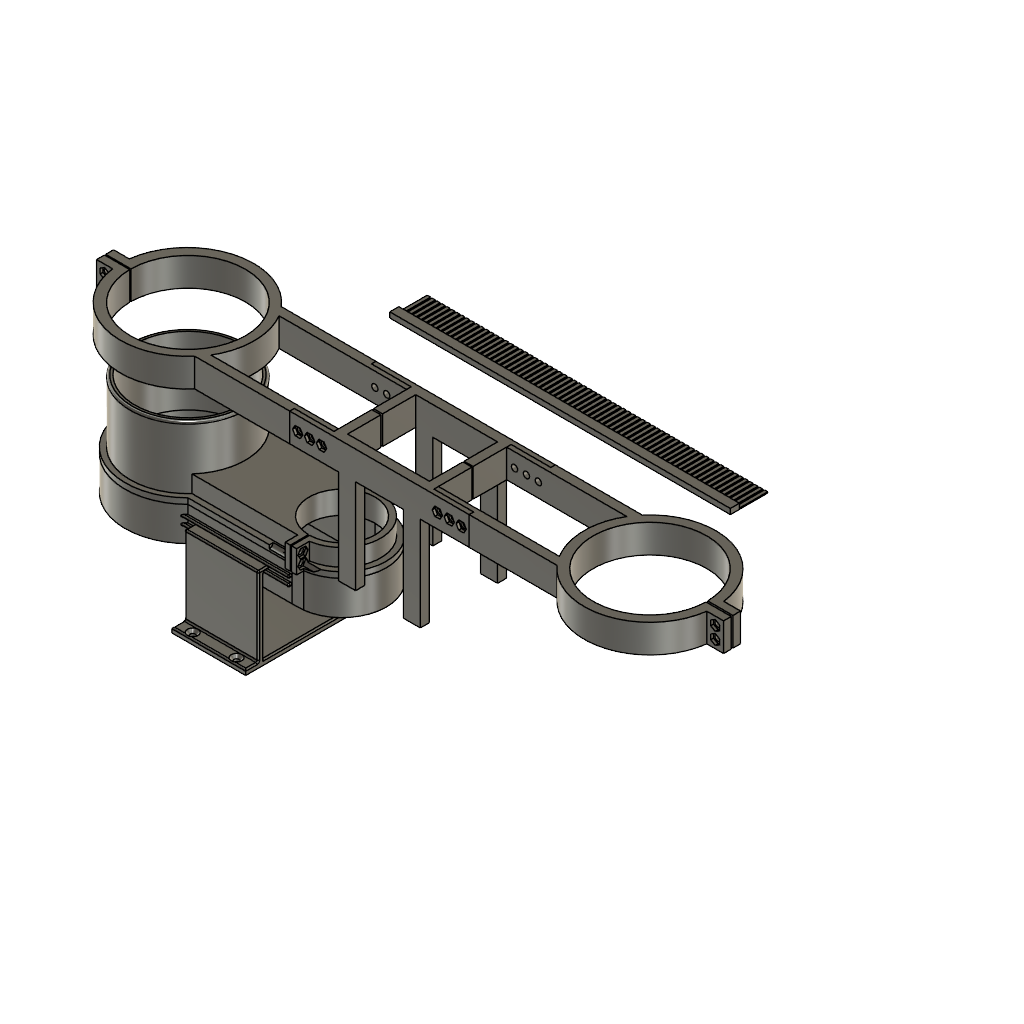
cnc-dust-shoe (Autodesk Fusion 360 design; units mm, degrees)
part number: 2026-10-06-19-06-41-625
Autodesk Fusion 360 part; units mm, degrees
(part 1 of 2)
sketch "Sketch1" plane through (0, 0, 0) normal (0, 0, 1) x (1, 0, 0)
  line L0 (-0.0662, 34.0001) -> (-170.0662, 34.0001)
  line L1 (-170.0662, 34.0001) -> (-170.0662, -34.0001)
  line L2 (-170.0662, -34.0001) -> (-5.0662, -34.0001)
  line L3 (4.9338, -33.6402) -> (4.9338, -44.9999)
  line L4 (-5.0662, -44.9999) -> (-5.0662, -34.0001)
  line L5 (-0.5662, -28.9945) -> (-0.5662, -44.9999)
  line L6 (0.4287, -28.9968) -> (0.4287, -44.9999)
  line L7 (4.9338, -44.9999) -> (0.4287, -44.9999)
  line L8 (-0.5662, -44.9999) -> (-5.0662, -44.9999)
  arc A0 (4.9338, -33.6402) -> (-0.0662, 34.0001) centre (0, 0) ccw
  arc A1 (0.4287, -28.9968) -> (-0.5662, -28.9945) centre (0, 0) ccw
  arc A2 (4.9338, -33.6402) -> (-5.0662, -33.6206) centre (0, 0) ccw
  line L9 (-5.0662, -34.0001) -> (-5.0662, -33.6206)
  dimension "d1" = 58
  dimension "d3" = 170
  constraint coincident A0.centre A1.centre
  constraint horizontal L0
  constraint vertical L1
  constraint horizontal L2
  constraint vertical L3
  constraint horizontal L7
  constraint vertical L4
  constraint collinear L7 L8
  constraint concentric A0 A1
  constraint vertical L5
  constraint vertical L6
  constraint concentric A0 A2
  constraint perpendicular L2 L9
  measures "d1" diameter of A1
  measures "d3" distance of L0.start L0.end
extrude "Extrude1" add sketch "Sketch1" along normal blind 20 makes body 1
sketch "Sketch2" plane through (0, 0, 20) normal (0, 0, 1) x (-1, 0, 0)
  arc A0 (-4.9338, 33.6402) -> (0.0662, -34.0001) centre (0, 0) ccw
  line L0 (0.0662, -34.0001) -> (170.0662, -34.0001)
  line L1 (170.0662, -34.0001) -> (170.0662, 34.0001)
  line L2 (170.0662, 34.0001) -> (5.0662, 34.0001)
  circle A1 centre (135.7962, 0.0001) radius 50.7
  circle A2 centre (135.7962, 0.0001) radius 46.7
  line L3 (5.0662, 34.0001) -> (5.0662, 44.9999)
  line L4 (5.0662, 44.9999) -> (0.5662, 44.9999)
  line L5 (0.5662, 44.9999) -> (0.5662, 28.9945)
  arc A3 (-0.4287, 28.9968) -> (0.5662, 28.9945) centre (0, 0) ccw
  line L6 (-0.4287, 28.9968) -> (-0.4287, 44.9999)
  line L7 (-0.4287, 44.9999) -> (-4.9338, 44.9999)
  line L8 (-4.9338, 44.9999) -> (-4.9338, 33.6402)
  circle A4 centre (135.7962, 0.0001) radius 55.2
  line L9 (98.1865, 34.0001) -> (5.0662, 34.0001)
  line L10 (5.0662, 34.0001) -> (5.0662, 39.0001)
  line L11 (5.0662, 39.0001) -> (98.1865, 39.0001)
  line L12 (98.1865, 39.0001) -> (98.1865, 34.0001)
  line L13 (0.0662, -34.0001) -> (96.7318, -34.0001)
  line L14 (96.7318, -34.0001) -> (96.7318, -39.0001)
  line L15 (96.7318, -39.0001) -> (0.0662, -39.0001)
  line L16 (0.0662, -39.0001) -> (0.0662, -34.0001)
  arc A5 (-4.9338, 38.6868) -> (0.0662, -39.0001) centre (0, 0) ccw
  point P0 (135.7962, 0.0001)
  dimension "d9" = 101.4
  dimension "d12" = -4
  dimension "d189" = 110.4
  dimension "d190" = 5
  dimension "d191" = 5
  dimension "d192" = 5
  constraint coincident P0 A1.centre
  constraint horizontal L9
  constraint vertical L10
  constraint horizontal L11
  constraint vertical L12
  constraint coincident A1 L9.start
  constraint coincident L2 L9.start
  constraint horizontal L13
  constraint vertical L14
  constraint horizontal L15
  constraint vertical L16
  constraint coincident A4 L14.end
  constraint coincident A0.end L0.start
  constraint coincident L8 A5.start
  measures "d9" diameter of A1
  measures "d189" diameter of A4
  measures "d190" distance of L9.start L11.end
  measures "d191" distance of A0.end L15.end
extrude "Extrude3" add sketch "Sketch2" along normal blind 40 and the other way blind 20 contours L0 L2 A1 A2 | L0 L1 L2 A1 A2 | L0 L1 L2 A2 | L0 A2 | L2 A2 | L0 L1 A2 | L1 L2 A2 | L1 A2 bodies 1
extrude "Extrude19" add sketch "Sketch2" along normal blind 5 from surface at -20 contours A0 L8 L16 A5 | L0 A4 L13 L15 L16 | L0 A4 L13 L14 | L0 A1 A4 L11 L12 L14 | L2 A4 L9 L11 L12 | L2 L3 A4 L9 L10 L11 bodies 1
sketch "Sketch5" plane through (0, 0, 60) normal (0, 0, 1) x (-1, 0, 0)
  circle A0 centre (135.7962, 0.0001) radius 46.7
extrude "Extrude5" cut sketch "Sketch5" against normal through all bodies 1
sketch "Sketch6" plane through (0, 0, 0) normal (0, 0, -1) x (1, 0, 0)
  line L0 (-170.0662, -34.0001) -> (-170.0662, 34.0001)
  line L1 (-0.0662, -34.0001) -> (-170.0662, -34.0001)
  line L2 (-170.0662, 34.0001) -> (-5.0662, 34.0001)
  circle A0 centre (-135.7962, 0.0001) radius 46.7
  line L3 (-0.5662, 28.9945) -> (-99.1962, 28.9945)
  line L4 (-99.1962, 28.9945) -> (-99.1962, -29.0055)
  line L5 (-99.1962, -29.0055) -> (-0.5662, -29.0055)
  line L6 (-0.5662, -29.0055) -> (-0.5662, 28.9945)
  arc A1 (-5.0662, 33.6206) -> (4.9338, 33.6402) centre (0, 0) ccw
  point P0 (-0.5662, 28.9945)
  dimension "d27" = 58
  constraint horizontal L3
  constraint vertical L4
  constraint horizontal L5
  constraint vertical L6
  constraint coincident A0 L4.end
  constraint coincident P0 L3.start
  measures "d27" distance of L3.end L4.end
extrude "Extrude6" cut sketch "Sketch6" against normal blind 18 contours L0 A0 | L0 L1 L2 A0 L3 L4 | L1 A0 | L2 A0 | A0 L3 L4 | A0 L3 L5 A1 bodies 1
sketch "Sketch7" plane through (4.9338, 0, 0) normal (1, 0, 0) x (0, 1, 0)
  line L0 (-44.9999, 0) -> (-38.6868, 0)
  line L1 (-33.6402, 5) -> (-33.6402, 20)
  line L2 (-33.6402, 20) -> (-44.9999, 20)
  line L3 (-44.9999, 20) -> (-44.9999, 0)
  line L4 (-33.6402, 0) -> (-44.9999, 0)
  line L5 (-41.5573, 18.1607) -> (-43.7945, 14.2857)
  line L6 (-43.7945, 14.2857) -> (-41.5573, 10.4107)
  line L7 (-41.5573, 10.4107) -> (-37.0829, 10.4107)
  line L8 (-37.0829, 10.4107) -> (-34.8456, 14.2857)
  line L9 (-34.8456, 14.2857) -> (-37.0829, 18.1607)
  line L10 (-37.0829, 18.1607) -> (-41.5573, 18.1607)
  line L11 (-41.5573, 9.5893) -> (-43.7945, 5.7143)
  line L12 (-43.7945, 5.7143) -> (-41.5573, 1.8393)
  line L13 (-41.5573, 1.8393) -> (-37.0829, 1.8393)
  line L14 (-37.0829, 1.8393) -> (-34.8456, 5.7143)
  line L15 (-34.8456, 5.7143) -> (-37.0829, 9.5893)
  line L16 (-37.0829, 9.5893) -> (-41.5573, 9.5893)
  circle A0 centre (-39.3201, 14.2857) radius 2.5
  circle A1 centre (-39.3201, 5.7143) radius 2.5
  circle A2 centre (-39.3201, 5.7143) radius 3.875
  line L17 (-38.6868, 0) -> (-38.6868, 5)
  line L18 (-38.6868, 5) -> (-33.6402, 5)
  point P0 (-39.3201, 14.2857)
  point P1 (-39.3201, 5.7143)
  point P2 (-39.3201, 14.2857)
  point P3 (-39.3201, 5.7143)
  dimension "d40" = 20
  dimension "d41" = 5.7143
  dimension "d43" = 3.875
  dimension "d44" = 3.875
  dimension "d45" = 5
  dimension "d46" = 5
  constraint coincident P2 P0
  constraint coincident P3 P1
  constraint concentric A1 A2
  constraint tangent L12 A2
  measures "d40" distance of L0.start L2.end
  measures "d41" distance of P3 L4
  measures "d43" distance of P2 L10
  measures "d44" distance of P3 L16
  measures "d45" diameter of A0
  measures "d46" diameter of A1
extrude "Extrude9" cut sketch "Sketch7" along normal mid plane 40 contours A1 L17 L18 | A1 L17 L18 | A0 bodies 1
extrude "Extrude10" cut sketch "Sketch7" along normal blind -2.25 and the other way blind -15 contours L13 L14 A2 L17 | L13 A2 L17 | L12 L13 A2 | A1 A2 L17 L18 | A1 A2 L17 L18 | L11 L12 A2 | L14 A2 L18 | L14 L15 A2 L18 | L11 L16 A2 | L15 L16 A2 | L5 L6 L7 L8 L9 L10 bodies 1
fillet "Fillet3" radius 2 curvature continuous 1 edges at (-88.5272, 18.3338, 60) on bodies 1
ref_plane "WorkPlane1" through (-30.9732, -5.4691, 90) normal (0, 0, 1) x (-1, 0, 0)
sketch "Sketch9" plane through (0, 0, 90) normal (0, 0, 1) x (1, 0, 0)
  circle A0 centre (-135.7962, -0.0001) radius 50.7
  line L0 (34.9038, 29.9999) -> (106.9038, 29.9999)
  line L1 (106.9038, -30.0001) -> (34.9038, -30.0001)
  line L2 (114.9038, -38.0001) -> (26.9038, -38.0001)
  line L3 (26.9038, 37.9999) -> (114.9038, 37.9999)
  line L4 (26.9038, -38.0001) -> (-91.8897, -38.0001)
  line L5 (26.9038, 37.9999) -> (-91.5487, 37.9999)
  line L6 (26.9038, 29.9718) -> (-85.4827, 29.9718)
  line L7 (26.9038, -29.972) -> (-85.4836, -29.972)
  arc A1 (-85.4836, -29.972) -> (-85.4827, 29.9718) centre (-136.4963, 0.0007) ccw
  line L8 (-208.7962, 7.4999) -> (-193.7962, 7.4999)
  line L9 (-193.7962, -7.5001) -> (-208.7962, -7.5001)
  arc A2 (-91.5487, 37.9999) -> (-194.8742, 7.4999) centre (-136.4963, 0.0007) ccw
  arc A3 (-194.6129, -7.5001) -> (-91.8897, -38.0001) centre (-136.4963, 0.0007) ccw
  line L10 (114.9038, 29.9999) -> (114.9038, 7.4999)
  line L11 (114.9038, -7.5001) -> (114.9038, -30.0001)
  line L12 (106.9038, -0.5001) -> (114.9038, -0.5001)
  line L13 (106.9038, 0.4999) -> (114.9038, 0.4999)
  line L14 (106.9038, 29.9999) -> (106.9038, 0.4999)
  line L15 (106.9038, -0.5001) -> (106.9038, -30.0001)
  line L16 (-186.4938, 0.4968) -> (-208.7962, 0.4966)
  line L17 (-186.4938, -0.5002) -> (-208.7962, -0.5002)
  line L18 (-208.7962, -7.5001) -> (-208.7962, -0.5002)
  line L19 (-208.7962, 0.4966) -> (-208.7962, 7.4999)
  arc A4 (-186.4938, -0.5002) -> (-186.4938, 0.4968) centre (-136.4963, 0.0007) ccw
  line L20 (114.9038, 37.9999) -> (226.4769, 37.9999)
  line L21 (227.3442, -38.0001) -> (114.9038, -38.0001)
  line L22 (114.9038, 29.9999) -> (220.7859, 29.9999)
  line L23 (221.3903, -30.0001) -> (114.9038, -30.0001)
  line L24 (114.9038, -30.0001) -> (114.9038, -0.5001)
  line L25 (114.9038, 0.4999) -> (114.9038, 29.9999)
  line L26 (106.9038, 0.4999) -> (345.5642, 0.4999) construction
  arc A5 (220.7859, 29.9999) -> (221.3903, -30.0001) centre (270.7233, 0.4999) ccw
  line L27 (328.2364, 7.9999) -> (343.0085, 7.9999)
  line L28 (343.0085, -7.0001) -> (328.2364, -7.0001)
  arc A6 (227.3442, -38.0001) -> (328.2364, -7.0001) centre (270.7233, 0.4999) ccw
  arc A7 (328.2364, 7.9999) -> (226.4769, 37.9999) centre (270.7233, 0.4999) ccw
  line L29 (343.0085, 1.2499) -> (320.7177, 1.2499)
  line L30 (343.0085, -0.25) -> (320.7177, -0.25)
  arc A8 (320.7177, 1.2499) -> (320.7177, -0.25) centre (270.7233, 0.4999) ccw
  line L31 (343.0085, 7.9999) -> (343.0085, 1.2499)
  line L32 (343.0085, -0.25) -> (343.0085, -7.0001)
  line L33 (34.9038, 0.7499) -> (26.9038, 0.7499)
  line L34 (34.9038, -0.7501) -> (26.9038, -0.7501)
  line L35 (26.9038, -29.972) -> (26.9038, -0.7501)
  line L36 (26.9038, 0.7499) -> (26.9038, 29.9718)
  line L37 (34.9038, -30.0001) -> (34.9038, -0.7501)
  line L38 (34.9038, 0.7499) -> (34.9038, 29.9999)
  line L39 (34.9038, 29.9999) -> (49.9038, 29.9999)
  line L40 (49.9038, 29.9999) -> (49.9038, 37.9999)
  line L41 (49.9038, 37.9999) -> (34.9038, 37.9999)
  line L42 (34.9038, 37.9999) -> (34.9038, 29.9999)
  line L43 (106.9038, 29.9999) -> (91.9038, 29.9999)
  line L44 (91.9038, 29.9999) -> (91.9038, 37.9999)
  line L45 (91.9038, 37.9999) -> (106.9038, 37.9999)
  line L46 (106.9038, 37.9999) -> (106.9038, 29.9999)
  line L47 (106.9038, -30.0001) -> (91.9038, -30.0001)
  line L48 (91.9038, -30.0001) -> (91.9038, -38.0001)
  line L49 (91.9038, -38.0001) -> (106.9038, -38.0001)
  line L50 (106.9038, -38.0001) -> (106.9038, -30.0001)
  line L51 (34.9038, -30.0001) -> (49.9038, -30.0001)
  line L52 (49.9038, -30.0001) -> (49.9038, -38.0001)
  line L53 (49.9038, -38.0001) -> (34.9038, -38.0001)
  line L54 (34.9038, -38.0001) -> (34.9038, -30.0001)
  line L55 (26.9038, 33.9999) -> (-8.0962, 33.9999)
  line L56 (-8.0962, 33.9999) -> (26.9038, 33.9999)
  line L57 (26.9038, 33.9999) -> (26.9038, 29.9718)
  line L58 (-8.0962, 33.9999) -> (-8.0962, 37.9999)
  line L59 (114.9038, -34.0001) -> (149.9038, -34.0001)
  line L60 (149.9038, -34.0001) -> (149.9038, -38.0001)
  line L61 (114.9038, -34.0001) -> (114.9038, -30.0001)
  line L62 (114.9038, 29.9999) -> (114.9038, 33.9999)
  line L63 (114.9038, 33.9999) -> (149.9038, 33.9999)
  line L64 (149.9038, 33.9999) -> (149.9038, 37.9999)
  line L65 (26.9038, -34.0001) -> (-8.0962, -34.0001)
  line L66 (-8.0962, -34.0001) -> (-8.0962, -38.0001)
  line L67 (26.9038, -34.0001) -> (26.9038, -29.972)
  point P0 (-135.7962, -0.0001)
  point P1 (-85.0962, -0.0001)
  point P2 (-185.9147, -0.0001)
  point P3 (106.9038, -0.0001)
  point P4 (129.9038, -0.0001)
  dimension "d65" = 72
  dimension "d66" = 60
  dimension "d67" = 120
  dimension "d69" = 8
  dimension "d70" = 8
  dimension "d71" = 8
  dimension "d72" = 8
  dimension "d73" = 100
  dimension "d79" = 15
  dimension "d80" = 15
  dimension "d81" = 15
  dimension "d92" = 76
  dimension "d95" = 100
  dimension "d97" = 8
  dimension "d99" = 8
  dimension "d128" = 15
  dimension "d129" = 8
  dimension "d130" = 15
  dimension "d131" = 8
  dimension "d132" = 15
  dimension "d133" = 8
  dimension "d134" = 15
  dimension "d135" = 8
  dimension "d138" = 35
  dimension "d139" = 4
  dimension "d140" = 35
  dimension "d141" = 4
  dimension "d142" = 35
  dimension "d143" = 4
  dimension "d152" = 35
  dimension "d153" = 4
  constraint horizontal L0
  constraint vertical L14
  constraint horizontal L1
  constraint vertical L37
  constraint coincident A0 P1
  constraint perpendicular L4 L35
  constraint perpendicular L5 L36
  constraint perpendicular L6 L38
  constraint perpendicular L7 L37
  constraint concentric A1 A4
  constraint concentric A1 A2
  constraint horizontal L8
  constraint horizontal L9
  constraint vertical L18
  constraint coincident L8 A2.end
  constraint concentric A2 A3
  constraint coincident L9 A3.start
  constraint collinear L10 L11
  constraint collinear L14 L15
  constraint coincident P3 L14
  constraint collinear L18 L19
  constraint coincident L17 A4.start
  constraint coincident A0 L16.start
  constraint horizontal L20
  constraint horizontal L21
  constraint vertical L24
  constraint collinear L24 L25
  constraint perpendicular L24 L26
  constraint coincident L26 A5.centre
  constraint concentric A6 A8
  constraint concentric A5 A7
  constraint horizontal L27
  constraint vertical L31
  constraint horizontal L28
  constraint concentric A6 A7
  constraint collinear L31 L32
  constraint collinear L35 L36
  constraint collinear L37 L38
  constraint horizontal L39
  constraint vertical L40
  constraint horizontal L41
  constraint vertical L42
  constraint horizontal L43
  constraint vertical L44
  constraint horizontal L45
  constraint vertical L46
  constraint horizontal L47
  constraint vertical L48
  constraint horizontal L49
  constraint vertical L50
  constraint horizontal L51
  constraint vertical L52
  constraint horizontal L53
  constraint vertical L54
  constraint perpendicular L36 L55
  constraint perpendicular L6 L57
  constraint coincident L5 L58.end
  constraint perpendicular L5 L58
  constraint perpendicular L24 L59
  constraint coincident L21 L60.end
  constraint perpendicular L21 L60
  constraint perpendicular L23 L61
  constraint perpendicular L22 L62
  constraint perpendicular L62 L63
  constraint coincident L20 L64.end
  constraint perpendicular L20 L64
  constraint perpendicular L35 L65
  constraint coincident L4 L66.end
  constraint perpendicular L4 L66
  constraint perpendicular L7 L67
  measures "d65" distance of L0.start L0.end
  measures "d66" distance of L0.start L1.end
  measures "d67" distance of P1 L37
  measures "d69" distance of L1 L2
  measures "d70" distance of L35 L37
  measures "d71" distance of L0 L3
  measures "d72" distance of L10 L14
  measures "d73" diameter of A4
  measures "d79" distance of L10.end L11.start
  measures "d80" distance of L8.start L8.end
  measures "d81" distance of L8.start L9.end
  measures "d92" distance of L3.end L2.start
  measures "d95" diameter of A8
  measures "d97" distance of L20 L22
  measures "d99" distance of L21 L23
  measures "d128" distance of L0.start L39.end
  measures "d129" distance of L0.start L41.end
  measures "d130" distance of L0.end L43.end
  measures "d131" distance of L0.end L45.end
  measures "d132" distance of L1.start L47.end
  measures "d133" distance of L1.start L49.end
  measures "d134" distance of L1.end L51.end
  measures "d135" distance of L1.end L53.end
  measures "d138" distance of L55.start L55.end
  measures "d139" distance of L5 L56
  measures "d140" distance of L59.start L59.end
  measures "d141" distance of L21 L59
  measures "d142" distance of L62.end L63.end
  measures "d143" distance of L20 L63
  measures "d152" distance of L65.start L65.end
  measures "d153" distance of L4 L65
extrude "Extrude12" add sketch "Sketch9" against normal blind 83 separate body contours L0 L3 L39 L40 L41 L42 | L1 L2 L51 L52 L53 L54 | L0 L3 L43 L44 L45 L46 | L1 L2 L47 L48 L49 L50 makes body 2 at (39.9038, 37.9999, 62.3333) makes body 3 at (44.9038, -30.0001, 62.3333) makes body 4 at (96.9038, 29.9999, 62.3333) makes body 5 at (101.9038, -30.0001, 62.3333)
extrude "Extrude13" add sketch "Sketch9" along normal blind 25 contours L3 L5 L33 L36 L38 L42 L55 L56 L57 L58 | L2 L4 L34 L35 L37 L54 L65 L66 L67 | L0 L3 L39 L40 L41 L42 | L1 L2 L51 L52 L53 L54 | L0 L3 L40 L44 | L1 L2 L48 L52 | L0 L3 L43 L44 L45 L46 | L1 L2 L47 L48 L49 L50 | L3 L10 L13 L14 L20 L25 L46 L62 L63 L64 | L2 L11 L12 L15 L21 L24 L50 L59 L60 L61 bodies 2 3 4 5
extrude "Extrude14" add sketch "Sketch9" along normal blind 25 separate body contours L20 L21 L22 L23 A5 L27 L28 A6 A7 L29 L30 A8 L31 L32 L59 L60 L61 L62 L63 L64 makes body 6
extrude "Extrude15" add sketch "Sketch9" along normal blind 25 separate body contours A0 L4 L5 L6 L7 A1 L8 L9 A2 A3 L16 L17 L18 L19 L55 L56 L57 L58 L65 L66 L67 makes body 7
sketch "Sketch11" plane through (0, -38.0001, 0) normal (0, -1, 0) x (1, 0, 0)
  line L0 (34.9038, 90) -> (34.9038, 7)
  line L1 (34.9038, 7) -> (49.9038, 7)
  line L2 (49.9038, 7) -> (49.9038, 90)
  line L3 (49.9038, 90) -> (91.9038, 90)
  line L4 (91.9038, 90) -> (91.9038, 7)
  line L5 (91.9038, 7) -> (106.9038, 7)
  line L6 (106.9038, 7) -> (106.9038, 90)
  line L7 (106.9038, 90) -> (149.9038, 90)
  line L8 (149.9038, 90) -> (149.9038, 115)
  line L9 (149.9038, 115) -> (-8.0962, 115)
  line L10 (-8.0962, 115) -> (-8.0962, 90)
  line L11 (-8.0962, 90) -> (34.9038, 90)
  line L12 (26.9038, 90) -> (26.9038, 115)
  line L13 (114.9038, 90) -> (114.9038, 115)
  line L14 (-3.3479, 106.4) -> (-5.5996, 102.5)
  line L15 (-5.5996, 102.5) -> (-3.3479, 98.6)
  line L16 (-3.3479, 98.6) -> (1.1554, 98.6)
  line L17 (1.1554, 98.6) -> (3.4071, 102.5)
  line L18 (3.4071, 102.5) -> (1.1554, 106.4)
  line L19 (1.1554, 106.4) -> (-3.3479, 106.4)
  line L20 (17.6521, 106.4) -> (15.4004, 102.5)
  line L21 (15.4004, 102.5) -> (17.6521, 98.6)
  line L22 (17.6521, 98.6) -> (22.1554, 98.6)
  line L23 (22.1554, 98.6) -> (24.4071, 102.5)
  line L24 (24.4071, 102.5) -> (22.1554, 106.4)
  line L25 (22.1554, 106.4) -> (17.6521, 106.4)
  line L26 (119.6521, 106.4) -> (117.4004, 102.5)
  line L27 (117.4004, 102.5) -> (119.6521, 98.6)
  line L28 (119.6521, 98.6) -> (124.1554, 98.6)
  line L29 (124.1554, 98.6) -> (126.4071, 102.5)
  line L30 (126.4071, 102.5) -> (124.1554, 106.4)
  line L31 (124.1554, 106.4) -> (119.6521, 106.4)
  line L32 (140.6521, 106.4) -> (138.4004, 102.5)
  line L33 (138.4004, 102.5) -> (140.6521, 98.6)
  line L34 (140.6521, 98.6) -> (145.1554, 98.6)
  line L35 (145.1554, 98.6) -> (147.4071, 102.5)
  line L36 (147.4071, 102.5) -> (145.1554, 106.4)
  line L37 (145.1554, 106.4) -> (140.6521, 106.4)
  line L38 (7.1521, 106.4) -> (4.9004, 102.5)
  line L39 (4.9004, 102.5) -> (7.1521, 98.6)
  line L40 (7.1521, 98.6) -> (11.6554, 98.6)
  line L41 (11.6554, 98.6) -> (13.9071, 102.5)
  line L42 (13.9071, 102.5) -> (11.6554, 106.4)
  line L43 (11.6554, 106.4) -> (7.1521, 106.4)
  line L44 (130.1521, 106.4) -> (127.9004, 102.5)
  line L45 (127.9004, 102.5) -> (130.1521, 98.6)
  line L46 (130.1521, 98.6) -> (134.6554, 98.6)
  line L47 (134.6554, 98.6) -> (136.9071, 102.5)
  line L48 (136.9071, 102.5) -> (134.6554, 106.4)
  line L49 (134.6554, 106.4) -> (130.1521, 106.4)
  point P0 (19.9038, 102.5)
  point P1 (-1.0962, 102.5)
  point P2 (121.9038, 102.5)
  point P3 (142.9038, 102.5)
  point P4 (132.4038, 102.5)
  point P5 (26.9038, 90)
  point P6 (-8.0962, 90)
  point P7 (-1.0962, 102.5)
  point P8 (19.9038, 102.5)
  point P9 (121.9038, 102.5)
  point P10 (142.9038, 102.5)
  point P11 (9.4038, 102.5)
  point P12 (142.9038, 102.5)
  point P13 (9.4038, 102.5)
  point P14 (132.4038, 102.5)
  dimension "d156" = 7
  dimension "d157" = 35
  dimension "d158" = 7
  dimension "d159" = 7
  dimension "d160" = 7
  dimension "d161" = 3.9
  dimension "d162" = 3.9
  dimension "d163" = 3.9
  dimension "d164" = 3.9
  dimension "d167" = 17.5
  dimension "d168" = 17.5
  dimension "d169" = 3.9
  dimension "d170" = 3.9
  constraint coincident P7 P1
  constraint coincident P8 P0
  constraint coincident P9 P2
  constraint coincident P12 P10
  constraint coincident P13 P11
  constraint coincident P14 P4
  measures "d156" distance of L10 P7
  measures "d157" distance of P5 P6
  measures "d158" distance of P8 L12
  measures "d159" distance of P9 L13
  measures "d160" distance of L8 P12
  measures "d161" distance of P7 L19
  measures "d162" distance of P8 L25
  measures "d163" distance of P9 L31
  measures "d164" distance of P12 L37
  measures "d167" distance of L10 P13
  measures "d168" distance of L8 P14
  measures "d169" distance of P13 L43
  measures "d170" distance of P14 L49
hole "Hole1" at (-1.0962, -38.0001, 102.5) at (19.9038, -38.0001, 102.5) at (121.9038, -38.0001, 102.5) at (132.4038, -38.0001, 102.5) at (9.4038, -38.0001, 102.5) at (142.9038, -38.0001, 102.5) direction (0, 1, 0) diameter 5.5 end through all bodies 2 3 6 7
extrude "Extrude16" cut sketch "Sketch11" against normal blind 2.5 contours L14 L15 L16 L17 L18 L19 | L20 L21 L22 L23 L24 L25 | L26 L27 L28 L29 L30 L31 | L32 L33 L34 L35 L36 L37 | L38 L39 L40 L41 L42 L43 | L44 L45 L46 L47 L48 L49 bodies 3
sketch "Sketch12" plane through (0, -7.0001, 0) normal (0, -1, 0) x (1, 0, 0)
  line L0 (328.2364, 90) -> (343.0085, 90)
  line L1 (343.0085, 90) -> (343.0085, 115)
  line L2 (343.0085, 115) -> (328.2364, 115)
  line L3 (328.2364, 115) -> (328.2364, 90)
  line L4 (343.0085, 90) -> (328.2364, 90)
  line L5 (331.7115, 110.0898) -> (331.7334, 105.5865)
  line L6 (331.7334, 105.5865) -> (335.6443, 103.3539)
  line L7 (335.6443, 103.3539) -> (339.5334, 105.6245)
  line L8 (339.5334, 105.6245) -> (339.5115, 110.1277)
  line L9 (339.5115, 110.1277) -> (335.6005, 112.3604)
  line L10 (335.6005, 112.3604) -> (331.7115, 110.0898)
  line L11 (331.7224, 94.8912) -> (335.6224, 92.6395)
  line L12 (335.6224, 92.6395) -> (339.5224, 94.8912)
  line L13 (339.5224, 94.8912) -> (339.5224, 99.3945)
  line L14 (339.5224, 99.3945) -> (335.6224, 101.6462)
  line L15 (335.6224, 101.6462) -> (331.7224, 99.3945)
  line L16 (331.7224, 99.3945) -> (331.7224, 94.8912)
  point P0 (335.6224, 107.8571)
  point P1 (335.6224, 97.1429)
  point P2 (335.6224, 107.8571)
  point P3 (335.6224, 97.1429)
  dimension "d171" = 25
  dimension "d172" = 7.1429
  dimension "d173" = 7.1429
  dimension "d174" = 3.9
  dimension "d175" = 3.9
  constraint coincident P2 P0
  constraint coincident P3 P1
  measures "d171" distance of L0.end L1.end
  measures "d172" distance of P3 L4
  measures "d173" distance of L2 P2
  measures "d174" distance of P2 L10
  measures "d175" distance of P3 L16
hole "Hole2" at (335.6224, -7.0001, 107.8571) at (335.6224, -7.0001, 97.1429) direction (0, 1, 0) diameter 5.5 end through all bodies 6
extrude "Extrude17" cut sketch "Sketch12" against normal blind 2.5 contours L5 L6 L7 L8 L9 L10 | L11 L12 L13 L14 L15 L16 bodies 6
sketch "Sketch13" plane through (0, -7.5001, 0) normal (0, -1, 0) x (1, 0, 0)
  line L0 (-208.7962, 90) -> (-194.6129, 90)
  line L1 (-194.6129, 90) -> (-194.6129, 115)
  line L2 (-194.6129, 115) -> (-208.7962, 115)
  line L3 (-208.7962, 115) -> (-208.7962, 90)
  line L4 (-193.7962, 90) -> (-208.7962, 90)
  line L5 (-205.6046, 105.6055) -> (-201.7046, 103.3538)
  line L6 (-201.7046, 103.3538) -> (-197.8046, 105.6055)
  line L7 (-197.8046, 105.6055) -> (-197.8046, 110.1088)
  line L8 (-197.8046, 110.1088) -> (-201.7046, 112.3605)
  line L9 (-201.7046, 112.3605) -> (-205.6046, 110.1088)
  line L10 (-205.6046, 110.1088) -> (-205.6046, 105.6055)
  line L11 (-205.6046, 94.8912) -> (-201.7046, 92.6395)
  line L12 (-201.7046, 92.6395) -> (-197.8046, 94.8912)
  line L13 (-197.8046, 94.8912) -> (-197.8046, 99.3945)
  line L14 (-197.8046, 99.3945) -> (-201.7046, 101.6462)
  line L15 (-201.7046, 101.6462) -> (-205.6046, 99.3945)
  line L16 (-205.6046, 99.3945) -> (-205.6046, 94.8912)
  point P0 (-201.7046, 107.8571)
  point P1 (-201.7046, 97.1429)
  point P2 (-201.7046, 107.8571)
  point P3 (-201.7046, 97.1429)
  dimension "d180" = 25
  dimension "d181" = 7.1429
  dimension "d182" = 7.1429
  dimension "d183" = 3.9
  dimension "d184" = 3.9
  constraint coincident P2 P0
  constraint coincident P3 P1
  measures "d180" distance of L0.start L2.end
  measures "d181" distance of P3 L4
  measures "d182" distance of L2 P2
  measures "d183" distance of P2 L10
  measures "d184" distance of P3 L16
hole "Hole3" at (-201.7046, -7.5001, 107.8571) at (-201.7046, -7.5001, 97.1429) direction (0, 1, 0) diameter 5.5 end through all bodies 7
extrude "Extrude18" cut sketch "Sketch13" against normal blind 2.5 contours L5 L6 L7 L8 L9 L10 | L11 L12 L13 L14 L15 L16 bodies 7
sketch "Sketch16" plane through (0, 0, 0) normal (0, 0, -1) x (1, 0, 0)
  line L0 (-99.1873, 28.9945) -> (-17.7575, 28.9945)
  line L1 (-0.5662, 28.9945) -> (-0.5662, 44.9999)
  line L2 (-0.5662, 44.9999) -> (-5.0662, 44.9999)
  line L3 (-5.0662, 44.9999) -> (-5.0662, 39.0001)
  arc A0 (-96.7317, 39.0001) -> (-96.7318, -39.0001) centre (-135.7962, 0.0001) ccw
  line L4 (4.9338, 38.6868) -> (4.9338, 44.9999)
  line L5 (4.9338, 44.9999) -> (0.4287, 44.9999)
  line L6 (0.4287, 44.9999) -> (0.4287, 28.9968)
  arc A1 (-0.5662, 28.9945) -> (0.4287, 28.9968) centre (0, 0) ccw
  line L7 (-17.7395, -29.0055) -> (-99.1962, -29.0055)
  arc A2 (-99.1873, 28.9945) -> (-99.1962, -29.0055) centre (-135.7962, 0.0001) ccw
  line L8 (0.4287, 28.9968) -> (-0.5662, 28.9945)
  line L9 (4.9338, 38.6868) -> (-5.0662, 39.0001)
  circle A3 centre (-14.33, 34.0001) radius 2.505
  circle A4 centre (-82.316, 34.0001) radius 2.505
  circle A5 centre (-149.9996, 49.0477) radius 2.505
  circle A6 centre (-186.9893, 0.2509) radius 2.505
  circle A7 centre (-150, -48.7822) radius 2.505
  circle A8 centre (-82.316, -34.0001) radius 2.505
  circle A9 centre (-14.33, -34.0001) radius 2.505
  circle A10 centre (34.1518, 0.6226) radius 2.505
  line L10 (-5.0662, 39.0001) -> (-96.7317, 39.0001)
  line L11 (-96.7318, -39.0001) -> (-0.0662, -39.0001)
  arc A11 (-0.0662, -39.0001) -> (4.9338, 38.6868) centre (0, 0) ccw
  arc A12 (-17.7575, 28.9945) -> (-17.7395, -29.0055) centre (0, 0) ccw
  line L12 (-17.7575, 28.9945) -> (-0.5662, 28.9945)
  line L13 (-17.7395, -29.0055) -> (0.0688, -28.9999)
  point P0 (-14.33, 34.0001)
  point P1 (-82.316, 34.0001)
  point P2 (-82.316, -34.0001)
  point P3 (-14.33, -34.0001)
  point P4 (34.1518, 0.6226)
  point P5 (-186.9893, 0.2509)
  point P6 (-149.9996, 49.0477)
  point P7 (-150, -48.7822)
  dimension "d206" = 5.01
  dimension "d207" = 5.01
  dimension "d208" = 5.01
  dimension "d209" = 5.01
  dimension "d210" = 5.01
  dimension "d211" = 5.01
  dimension "d212" = 5.01
  dimension "d213" = 5.01
  constraint coincident L6.end A1.end
  constraint coincident L1.start A1.start
  constraint coincident L4.start L9.start
  constraint coincident L3.end L9.end
  constraint coincident P0 A3.centre
  constraint coincident P1 A4.centre
  constraint coincident P6 A5.centre
  constraint coincident P5 A6.centre
  constraint coincident P7 A7.centre
  constraint coincident P2 A8.centre
  constraint coincident P3 A9.centre
  constraint coincident P4 A10.centre
  constraint coincident L0.end A12.start
  constraint coincident L7.start A12.end
  constraint midpoint A1 L13.end
  measures "d206" diameter of A3
  measures "d207" diameter of A4
  measures "d208" diameter of A5
  measures "d209" diameter of A6
  measures "d210" diameter of A7
  measures "d211" diameter of A8
  measures "d212" diameter of A9
  measures "d213" diameter of A10
extrude "Extrude21" add sketch "Sketch16" along normal blind 30 separate body contours L0 L1 A0 L6 A1 L7 A2 L9 L10 L11 A11 L12 L13 | L1 L6 L8 L9 | A3 | A4 | A5 | A6 | A7 | A8 | A9 | A10 makes body 8
sketch "Sketch17" plane through (0, 0, -30) normal (0, 0, -1) x (1, 0, 0)
  line L0 (4.9338, 38.6868) -> (-5.0662, 39.0001)
  circle A0 centre (-135.7962, 0.0001) radius 55.2
  circle A1 centre (-135.7962, 0.0001) radius 46.7
  arc A2 (0.0688, -28.9999) -> (0.4287, 28.9968) centre (0, 0) ccw
  arc A3 (-99.1873, 28.9945) -> (-99.1962, -29.0055) centre (-135.7962, 0.0001) ccw
  line L1 (-99.1873, 28.9945) -> (-0.5662, 28.9945)
  line L2 (0.0688, -28.9999) -> (-17.7395, -29.0055)
  line L3 (-17.7395, -29.0055) -> (-99.1962, -29.0055)
  arc A4 (-0.0662, -39.0001) -> (4.9338, 38.6868) centre (0, 0) ccw
  line L4 (-5.0662, 39.0001) -> (-96.7317, 39.0001)
  arc A5 (-96.7317, 39.0001) -> (-96.7318, -39.0001) centre (-135.7962, 0.0001) ccw
  line L5 (-96.7318, -39.0001) -> (-0.0662, -39.0001)
  line L6 (-0.5662, 28.9945) -> (0.4287, 28.9968)
extrude "Extrude22" add sketch "Sketch17" against normal blind 10 contours A1 A3 bodies 8
extrude "Extrude24" cut sketch "Sketch7" against normal blind 20 from surface at -10 contours A1 A2 L17 L18 | A1 A2 L17 L18 | A1 L17 L18 | A1 L17 L18 bodies 1
hole "Hole4" at (-82.316, -34.0001, 0) at (-149.9996, -49.0477, 0) at (-186.9893, -0.2509, 0) at (-150, 48.7822, 0) at (-82.316, 34.0001, 0) at (-14.33, 34.0001, 0) at (-14.33, -34.0001, 0) at (34.1518, -0.6226, 0) direction (0, 0, 1) diameter 5.01 depth 3.01 tip angle 118 bodies 1
sketch "Sketch18" plane through (0, -39.0001, 0) normal (0, -1, 0) x (1, 0, 0)
  line L0 (-5.0662, -7.6088) -> (-100.0662, -7.6088)
  line L1 (-100.0662, -7.6088) -> (-100.0662, -10.1088)
  line L2 (-100.0662, -10.1088) -> (-5.0662, -10.1088)
  line L3 (-5.0662, -10.1088) -> (-5.0662, -7.6088)
  line L4 (-100.0662, -16.6088) -> (-5.0662, -16.6088)
  line L5 (-5.0662, -16.6088) -> (-5.0662, -14.1088)
  line L6 (-5.0662, -14.1088) -> (-100.0662, -14.1088)
  line L7 (-100.0662, -14.1088) -> (-100.0662, -16.6088)
  dimension "d224" = 95
  dimension "d225" = 2.5
  dimension "d226" = 95
  dimension "d227" = 2.5
  dimension "d228" = 4
  constraint horizontal L0
  constraint vertical L1
  constraint horizontal L2
  constraint vertical L3
  constraint horizontal L6
  constraint vertical L7
  constraint horizontal L4
  constraint vertical L5
  measures "d224" distance of L0.start L0.end
  measures "d225" distance of L0.start L2.end
  measures "d226" distance of L5.end L6.end
  measures "d227" distance of L4.end L5.end
  measures "d228" distance of L2 L6
extrude "Extrude25" add sketch "Sketch18" along normal blind 3 bodies 8
fillet "Fillet4" radius 1.2 10 edges at (-52.5214, -42.0001, -7.6088) (-52.5214, -42.0001, -10.1088) (-5.0662, -42.0001, -8.8588) (-5.0662, -40.5001, -7.6088) (-5.0662, -40.5001, -10.1088) (-52.5214, -42.0001, -14.1088) (-52.5214, -42.0001, -16.6088) (-5.0662, -40.5001, -14.1088) (-5.0662, -42.0001, -15.3588) (-5.0662, -40.5001, -16.6088) on bodies 8
sketch "Sketch19" plane through (0, 39.0001, 0) normal (0, 1, 0) x (-1, 0, 0)
  line L0 (100.0662, -10.1088) -> (5.0662, -10.1088)
  line L1 (5.0662, -10.1088) -> (5.0662, -7.6088)
  line L2 (100.0662, -7.6088) -> (100.0662, -10.1088)
  line L3 (5.0662, -7.6088) -> (100.0662, -7.6088)
  line L4 (100.0662, -16.6088) -> (5.0662, -16.6088)
  line L5 (5.0662, -16.6088) -> (5.0662, -14.1088)
  line L6 (100.0662, -14.1088) -> (100.0662, -16.6088)
  line L7 (5.0662, -14.1088) -> (100.0662, -14.1088)
  line L8 (5.0662, -7.6088) -> (100.0662, -7.6088)
  line L9 (100.0662, -7.6088) -> (100.0662, -10.1088)
  line L10 (100.0662, -10.1088) -> (5.0662, -10.1088)
  line L11 (5.0662, -10.1088) -> (5.0662, -7.6088)
  line L12 (5.0662, -14.1088) -> (100.0662, -14.1088)
  line L13 (100.0662, -14.1088) -> (100.0662, -16.6088)
  line L14 (100.0662, -16.6088) -> (5.0662, -16.6088)
  line L15 (5.0662, -16.6088) -> (5.0662, -14.1088)
  constraint horizontal L8
  constraint vertical L9
  constraint horizontal L10
  constraint vertical L11
  constraint coincident L0.start L2.end
  constraint coincident L1.end L3.start
  constraint horizontal L12
  constraint vertical L13
  constraint horizontal L14
  constraint vertical L15
  constraint coincident L4.start L6.end
  constraint coincident L5.end L7.start
extrude "Extrude26" add sketch "Sketch19" along normal blind 3 bodies 8
fillet "Fillet5" radius 1.2 10 edges at (-52.5215, 42.0001, -7.6088) (-52.5215, 42.0001, -10.1088) (-5.0662, 42.0001, -8.8588) (-52.5215, 42.0001, -14.1088) (-52.5215, 42.0001, -16.6088) (-5.0662, 42.0001, -15.3588) (-5.0662, 40.5001, -14.1088) (-5.0662, 40.5001, -16.6088) (-5.0662, 40.5001, -10.1088) (-5.0662, 40.5001, -7.6088) on bodies 8
sketch "Sketch22" plane through (0, 0, -30) normal (0, 0, -1) x (1, 0, 0)
  line L0 (4.9338, 38.6868) -> (-5.0662, 39.0001)
  line L1 (-5.2991, 37.0064) -> (-97.4317, 37.092)
  arc A0 (-96.7036, 38.9805) -> (-94.8028, -36.9781) centre (-135.7963, -0.0008) ccw
  line L2 (-94.8028, -36.9781) -> (-0.0589, -37.0006)
  arc A1 (-0.0589, -37.0006) -> (4.759, 36.6913) centre (-0.0168, 0.0001) ccw
  line L3 (4.759, 36.6913) -> (-5.2991, 37.0064)
  line L4 (-5.3797, 32.0065) -> (-97.2349, 32.0918)
  line L5 (-93.2775, -31.9785) -> (-0.058, -32.0006)
  arc A2 (-0.058, -32.0006) -> (4.3481, 31.7017) centre (-0.0168, 0.0001) ccw
  line L6 (4.3481, 31.7017) -> (-5.3797, 32.0065)
  arc A3 (-103.5382, 29.5243) -> (-107.4505, -26.0849) centre (-81.2217, 0.012) ccw
  arc A4 (-104.6365, 34.9601) -> (-109.9836, -30.6861) centre (-81.2217, 0.012) ccw
  line L7 (-104.6365, 34.9601) -> (-103.094, 35.7418)
  arc A5 (-99.7649, -32.0156) -> (-99.7513, -32.0002) centre (-135.7963, -0.0008) ccw
  arc A6 (-99.7514, 32) -> (-99.7652, 32.0155) centre (-135.7963, -0.0008) ccw
  arc A7 (-103.4533, 35.7245) -> (-103.4364, -35.7109) centre (-135.7963, -0.0008) ccw
  line L8 (-97.2349, 32.0918) -> (-103.5382, 29.5243)
  arc A8 (-97.4317, 37.092) -> (-103.094, 35.7418) centre (-97.4433, 24.592) ccw
  line L9 (-97.8674, -36.5283) -> (-94.8028, -36.9781)
  arc A9 (-107.4505, -26.0849) -> (-93.2775, -31.9785) centre (-93.2727, -11.9785) ccw
  arc A10 (-109.9836, -30.6861) -> (-97.8674, -36.5283) centre (-94.5999, -14.2668) ccw
  arc A11 (0.0688, -28.9999) -> (0.4287, 28.9968) centre (0, 0) ccw
  line L10 (-99.1873, 28.9945) -> (-0.5662, 28.9945)
  line L11 (0.0688, -28.9999) -> (-17.7395, -29.0055)
  line L12 (-17.7395, -29.0055) -> (-99.1962, -29.0055)
  arc A12 (-0.0662, -39.0001) -> (4.9338, 38.6868) centre (0, 0) ccw
  line L13 (-5.0662, 39.0001) -> (-96.7317, 39.0001)
  arc A13 (-96.7317, 39.0001) -> (-96.7318, -39.0001) centre (-135.7962, 0.0001) ccw
  line L14 (-96.7318, -39.0001) -> (-0.0662, -39.0001)
  line L15 (-0.5662, 28.9945) -> (0.4287, 28.9968)
  arc A14 (-99.1962, -29.0055) -> (-99.1873, 28.9945) centre (-135.7962, 0.0001) ccw
  dimension "d278" = 74
  dimension "d282" = 5
  dimension "d283" = 5
  dimension "d284" = 5
  dimension "d287" = 2
  dimension "d288" = 12.5
  dimension "d289" = 20
  dimension "d290" = 22.5
  constraint concentric A0 A7
  constraint concentric A1 A2
  constraint concentric A5 A7
  constraint coincident A4 A7.start
  constraint concentric A6 A7
  constraint concentric A3 A4
  constraint coincident L7 A0.start
  constraint tangent L1 A8
  constraint tangent L7 A8
  constraint tangent A3 A9
  constraint tangent L5 A9
  constraint coincident A7.end L9
  constraint coincident A4 A7.end
  constraint tangent A4 A10
  constraint tangent L9 A10
  measures "d278" diameter of A3
  measures "d282" distance of L1 L4
  measures "d283" distance of L2 L5
  measures "d284" distance of L3 L6
  measures "d287" distance of L0 L3
  measures "d288" radius of A8
  measures "d289" radius of A9
  measures "d290" radius of A10
extrude "Extrude28" cut sketch "Sketch22" against normal blind 9 contours L1 L2 A1 L3 A4 L7 A8 L9 A10 bodies 8
sketch "Sketch20" plane through (-5.0662, 0, 0) normal (1, 0, 0) x (0, 1, 0)
  line L0 (-39.0001, -7.6088) -> (-40.8001, -7.6088)
  line L1 (-40.8001, -8.8088) -> (-40.8001, -7.6088)
  line L2 (-40.8001, -8.8088) -> (-39.0001, -8.8088)
  line L3 (-42.0001, -8.8088) -> (-40.8001, -8.8088)
  line L4 (-40.8001, -8.8088) -> (-40.8001, -7.6088)
  arc A0 (-40.8001, -7.6088) -> (-42.0001, -8.8088) centre (-40.8001, -8.8088) ccw
  arc A1 (-42.0001, -8.9088) -> (-40.8001, -10.1088) centre (-40.8001, -8.9088) ccw
  line L5 (-40.8001, -10.1088) -> (-40.8001, -8.9088)
  line L6 (-40.8001, -8.9088) -> (-42.0001, -8.9088)
  line L7 (-39.0001, -8.9088) -> (-40.8001, -8.9088)
  line L8 (-40.8001, -10.1088) -> (-40.8001, -8.9088)
  line L9 (-40.8001, -10.1088) -> (-39.0001, -10.1088)
  line L10 (-39.0001, -14.1088) -> (-40.8001, -14.1088)
  line L11 (-40.8001, -15.3088) -> (-40.8001, -14.1088)
  line L12 (-40.8001, -15.3088) -> (-39.0001, -15.3088)
  line L13 (-42.0001, -15.3088) -> (-40.8001, -15.3088)
  line L14 (-40.8001, -15.3088) -> (-40.8001, -14.1088)
  arc A2 (-40.8001, -14.1088) -> (-42.0001, -15.3088) centre (-40.8001, -15.3088) ccw
  arc A3 (-42.0001, -15.4088) -> (-40.8001, -16.6088) centre (-40.8001, -15.4088) ccw
  line L15 (-40.8001, -16.6088) -> (-40.8001, -15.4088)
  line L16 (-40.8001, -15.4088) -> (-42.0001, -15.4088)
  line L17 (-39.0001, -15.4088) -> (-40.8001, -15.4088)
  line L18 (-40.8001, -16.6088) -> (-40.8001, -15.4088)
  line L19 (-40.8001, -16.6088) -> (-39.0001, -16.6088)
  line L20 (39.0001, -8.8088) -> (40.8001, -8.8088)
  line L21 (40.8001, -7.6088) -> (40.8001, -8.8088)
  line L22 (40.8001, -7.6088) -> (39.0001, -7.6088)
  arc A4 (42.0001, -8.8088) -> (40.8001, -7.6088) centre (40.8001, -8.8088) ccw
  line L23 (40.8001, -7.6088) -> (40.8001, -8.8088)
  line L24 (40.8001, -8.8088) -> (42.0001, -8.8088)
  line L25 (42.0001, -8.9088) -> (40.8001, -8.9088)
  line L26 (40.8001, -8.9088) -> (40.8001, -10.1088)
  arc A5 (40.8001, -10.1088) -> (42.0001, -8.9088) centre (40.8001, -8.9088) ccw
  line L27 (39.0001, -10.1088) -> (40.8001, -10.1088)
  line L28 (40.8001, -8.9088) -> (40.8001, -10.1088)
  line L29 (40.8001, -8.9088) -> (39.0001, -8.9088)
  line L30 (39.0001, -15.3088) -> (40.8001, -15.3088)
  line L31 (40.8001, -14.1088) -> (40.8001, -15.3088)
  line L32 (40.8001, -14.1088) -> (39.0001, -14.1088)
  arc A6 (42.0001, -15.3088) -> (40.8001, -14.1088) centre (40.8001, -15.3088) ccw
  line L33 (40.8001, -14.1088) -> (40.8001, -15.3088)
  line L34 (40.8001, -15.3088) -> (42.0001, -15.3088)
  line L35 (42.0001, -15.4088) -> (40.8001, -15.4088)
  line L36 (40.8001, -15.4088) -> (40.8001, -16.6088)
  arc A7 (40.8001, -16.6088) -> (42.0001, -15.4088) centre (40.8001, -15.4088) ccw
  line L37 (39.0001, -16.6088) -> (40.8001, -16.6088)
  line L38 (40.8001, -15.4088) -> (40.8001, -16.6088)
  line L39 (40.8001, -15.4088) -> (39.0001, -15.4088)
  line L40 (-38.6868, 0) -> (39.0001, 0)
  line L41 (-38.6868, 0) -> (-38.6868, -30)
  line L42 (-38.6868, -30) -> (39.0001, -30)
  line L43 (39.0001, -30) -> (39.0001, 0)
  line L44 (-38.6868, -10.8588) -> (-48.6868, -10.8588)
  line L45 (-48.6868, -10.8588) -> (-48.6868, -13.3588)
  line L46 (-43.6868, -13.3588) -> (-38.6868, -13.3588)
  line L47 (-38.6868, -13.3588) -> (-38.6868, -10.8588)
  line L48 (0, 0) -> (0.1567, -30) construction
  line L49 (-43.6868, -13.3588) -> (-43.6868, -79.8588)
  line L50 (-48.6868, -79.8588) -> (-48.6868, -13.3588)
  line L51 (39.0001, -10.8588) -> (49.0001, -10.8588)
  line L52 (49.0001, -10.8588) -> (49.0001, -13.3588)
  line L53 (44.0001, -13.3588) -> (39.0001, -13.3588)
  line L54 (39.0001, -13.3588) -> (39.0001, -10.8588)
  line L55 (44.0001, -13.3588) -> (44.0001, -79.8588)
  line L56 (49.0001, -79.8588) -> (49.0001, -13.3588)
  line L57 (60.1566, -79.8588) -> (60.1566, -84.3588)
  line L58 (60.1566, -84.3588) -> (-59.8434, -84.3588)
  line L59 (-59.8434, -84.3588) -> (-59.8434, -79.8588)
  line L60 (-59.8434, -79.8588) -> (-48.6868, -79.8588)
  line L61 (-43.6868, -79.8588) -> (44.0001, -79.8588)
  line L62 (49.0001, -79.8588) -> (60.1566, -79.8588)
  line L63 (-39.0001, -8.8088) -> (-39.0001, -7.6088)
  line L64 (-39.0001, -10.1088) -> (-39.0001, -8.9088)
  line L65 (-39.0001, -15.3088) -> (-39.0001, -14.1088)
  line L66 (-39.0001, -16.6088) -> (-39.0001, -15.4088)
  line L67 (39.0001, -8.8088) -> (39.0001, -7.6088)
  line L68 (39.0001, -10.1088) -> (39.0001, -8.9088)
  line L69 (39.0001, -15.3088) -> (39.0001, -14.1088)
  line L70 (39.0001, -16.6088) -> (39.0001, -15.4088)
  point P0 (-39.0001, -10.1088)
  point P1 (-39.0001, -14.1088)
  point P2 (39.0001, 0)
  point P3 (-39.0001, -7.6088)
  point P4 (-39.0001, 0)
  dimension "d237" = 10
  dimension "d238" = 2.5
  dimension "d239" = 4
  dimension "d240" = 0.75
  dimension "d241" = 5
  dimension "d242" = 66.5
  dimension "d243" = 7.6088
  dimension "d244" = 7.6088
  dimension "d245" = 10
  dimension "d246" = 10
  dimension "d247" = 2.5
  dimension "d248" = 4
  dimension "d249" = 0.75
  dimension "d250" = 5
  dimension "d251" = 66.5
  dimension "d252" = 120
  dimension "d253" = 4.5
  dimension "d255" = 97.6868
  dimension "d256" = 11.1566
  dimension "d257" = 11.1566
  constraint horizontal L44
  constraint vertical L45
  constraint horizontal L46
  constraint vertical L47
  constraint coincident L41 L44.start
  constraint coincident L48.start origin
  constraint midpoint L42 L48.end
  constraint vertical L49
  constraint vertical L50
  constraint horizontal L51
  constraint vertical L52
  constraint horizontal L53
  constraint vertical L54
  constraint coincident L43 L51.start
  constraint vertical L55
  constraint vertical L56
  constraint horizontal L60
  constraint vertical L57
  constraint horizontal L58
  constraint vertical L59
  constraint collinear L60 L61
  constraint collinear L61 L62
  measures "d237" distance of L44.start L44.end
  measures "d238" distance of L44.start L46.end
  measures "d239" distance of P0 P1
  measures "d240" distance of L9 L44
  measures "d241" distance of L45.end L46.start
  measures "d242" distance of L45.end L50.start
  measures "d243" distance of L22.end P2
  measures "d244" distance of P3 P4
  measures "d245" distance of L44.start L44.end
  measures "d246" distance of L51.start L51.end
  measures "d247" distance of L51.start L53.end
  measures "d248" distance of L27.start L32.end
  measures "d249" distance of L27 L51
  measures "d250" distance of L52.end L53.start
  measures "d251" distance of L52.end L56.start
  measures "d252" distance of L59.end L57.start
  measures "d253" distance of L59.end L58.end
  measures "d255" distance of L50.start L56.start
  measures "d256" distance of L56.start L57.start
  measures "d257" distance of L50.start L59.end
extrude "Extrude27" add sketch "Sketch20" along normal blind 65 separate body contours L41 L43 L44 L45 L46 L47 L49 L50 L51 L52 L53 L54 L55 L56 L57 L58 L59 L60 L61 L62 makes body 9
fillet "Fillet6" radius 1.2 36 edges at (59.9338, -43.6868, -46.6088) (59.9338, -48.6868, -45.3588) (59.9338, 44.0001, -46.6088) (59.9338, 49.0001, -45.3588) (59.9338, -41.1868, -13.3588) (59.9338, -43.6868, -10.8588) (59.9338, -38.6868, -12.1088) (27.4338, -38.6868, -13.3588) (27.4338, -38.6868, -10.8588) (59.9338, 41.5001, -13.3588) (59.9338, 44.0001, -10.8588) (59.9338, 39.0001, -12.1088) (27.4338, 39.0001, -10.8588) (27.4338, 39.0001, -13.3588) (59.9338, 0.1566, -79.8588) (59.9338, -54.2651, -79.8588) (27.4338, -59.8434, -79.8588) (27.4338, -48.6868, -79.8588) (-5.0662, -48.6868, -45.3588) (27.4338, -48.6868, -10.8588) (27.4338, 49.0001, -10.8588) (-5.0662, 49.0001, -45.3588) (59.9338, 54.5784, -79.8588) (27.4338, 60.1566, -79.8588) (-5.0662, 54.5784, -79.8588) (27.4338, 49.0001, -79.8588) (-5.0662, 44.0001, -46.6088) (-5.0662, 0.1566, -79.8588) (-5.0662, -43.6868, -46.6088) (-5.0662, -54.2651, -79.8588) (-5.0662, 41.5001, -13.3588) (-5.0662, 39.0001, -12.1088) (-5.0662, 44.0001, -10.8588) (-5.0662, -43.6868, -10.8588) (-5.0662, -41.1868, -13.3588) (-5.0662, -38.6868, -12.1088) on bodies 9
fillet "Fillet6" radius 1.2 2 edges at (27.4338, 44.0001, -13.3588) (27.4338, -43.6868, -13.3588) on bodies 9
sketch "Sketch21" plane through (0, 0, -79.8588) normal (0, 0, 1) x (-1, 0, 0)
  line L0 (3.8662, 49.8868) -> (3.8662, 58.6434)
  line L1 (3.8662, 58.6434) -> (-58.7338, 58.6434)
  line L2 (-58.7338, 58.6434) -> (-58.7338, 49.8868)
  line L3 (-58.7338, 49.8868) -> (3.8662, 49.8868)
  line L4 (3.8662, -58.9566) -> (3.8662, -50.2001)
  line L5 (3.8662, -50.2001) -> (-58.7338, -50.2001)
  line L6 (-58.7338, -50.2001) -> (-58.7338, -58.9566)
  line L7 (-58.7338, -58.9566) -> (3.8662, -58.9566)
  point P0 (-46.7338, 54.6434)
  point P1 (-8.1338, 54.6434)
  point P2 (-46.7338, -54.9566)
  point P3 (-8.1338, -54.9566)
  dimension "d264" = 4
  dimension "d265" = 4
  dimension "d266" = 4
  dimension "d267" = 4
  dimension "d268" = 12
  dimension "d269" = 12
  dimension "d270" = 12
  dimension "d271" = 12
  measures "d264" distance of L7 P2
  measures "d265" distance of L7 P3
  measures "d266" distance of L1 P1
  measures "d267" distance of L1 P0
  measures "d268" distance of L6 P2
  measures "d269" distance of L4 P3
  measures "d270" distance of L2 P0
  measures "d271" distance of L0 P1
hole "Hole5" at (46.7338, -54.6434, -79.8588) at (8.1338, -54.6434, -79.8588) at (46.7338, 54.9566, -79.8588) at (8.1338, 54.9566, -79.8588) direction (0, 0, -1) diameter 4.5 end through all countersink diameter 9.4 countersink angle 90 bodies 9
move_body "Move1" bodies 9 to x (1, 0, 0) y (0, 1, 0) z (0, 0, 1) at (-95, 0, 0)
move_body "Move2" bodies 9 to x (1, 0, 0) y (0, 1, 0) z (0, 0, 1) at (10, 0, 0)
hole "Hole6" at (-14.33, -34.0001, 0) at (-82.316, -34.0001, 0) at (-82.316, 34.0001, 0) at (-14.33, 34.0001, 0) at (34.1518, -0.6226, 0) at (-150, 48.7822, 0) at (-186.9893, -0.2509, 0) at (-149.9996, -49.0477, 0) direction (0, 0, -1) diameter 5.02 depth 3 tip angle 118 bodies 8
sketch "Sketch23" plane through (0, 0, -30) normal (0, 0, -1) x (1, 0, 0)
  arc A0 (-103.5382, 29.5243) -> (-107.4505, -26.0849) centre (-81.2217, 0.012) ccw
  arc A1 (-107.4505, -26.0849) -> (-93.2775, -31.9785) centre (-93.2727, -11.9785) ccw
  line L0 (-93.2775, -31.9785) -> (-0.058, -32.0006)
  arc A2 (-0.058, -32.0006) -> (4.3481, 31.7017) centre (-0.0168, 0.0001) ccw
  line L1 (4.3481, 31.7017) -> (-5.3797, 32.0065)
  line L2 (-5.3797, 32.0065) -> (-97.2349, 32.0918)
  line L3 (-97.2349, 32.0918) -> (-103.5382, 29.5243)
  line L4 (-99.1873, 28.9945) -> (-0.5662, 28.9945)
  line L5 (-0.5662, 28.9945) -> (0.4287, 28.9968)
  arc A3 (0.0688, -28.9999) -> (0.4287, 28.9968) centre (0, 0) ccw
  line L6 (0.0688, -28.9999) -> (-17.7395, -29.0055)
  line L7 (-17.7395, -29.0055) -> (-99.1962, -29.0055)
  arc A4 (-99.1962, -29.0055) -> (-99.1873, 28.9945) centre (-135.7962, 0.0001) ccw
  circle A5 centre (-81.2217, 0.012) radius 33.5239
  line L8 (-98.8308, 28.5386) -> (-98.07, 28.9945)
  line L9 (-98.0095, -29.0055) -> (-98.8183, -28.5223)
  constraint concentric A0 A5
  constraint coincident A5 L8.start
  constraint coincident A4 L8.start
  constraint coincident A5 L8.end
  constraint coincident L4 L8.end
  constraint coincident A5 L9.start
  constraint coincident L7 L9.start
  constraint coincident A4 L9.end
  constraint coincident A5 L9.end
extrude "Extrude29" cut sketch "Sketch23" against normal blind 10 contours A4 A5 bodies 8
extrude "Extrude30" add sketch "Sketch23" against normal blind 10 contours L4 A4 A5 | L7 A4 A5 bodies 8